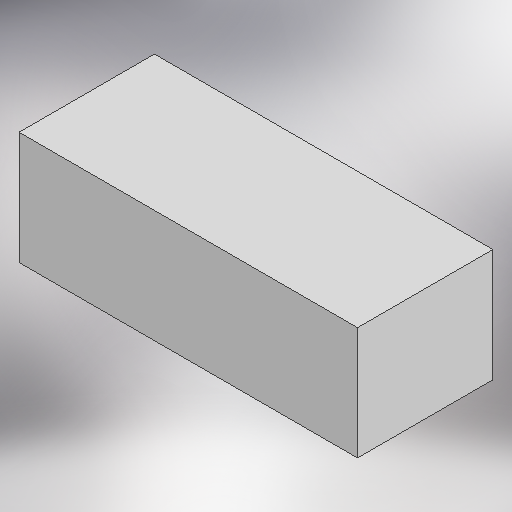
# Autodesk Inventor part: new_linked
Saved by Autodesk Inventor 2026 (Build 300175000, 175)
## iProperties
Created: 2026-10-20
Part Number: new_linked
Material: Generic
Document SubType Name: Modeling
Designer: 2ndlo
Density: 1 g/cm^3
Appearance: Default
Author: 2ndlo
Autodesk Inventor part; units mm, degrees
ref_plane "YZ Plane" through (0, 0, 0) normal (1, 0, 0) x (0, 1, 0)
ref_plane "XZ Plane" through (0, 0, 0) normal (0, 1, 0) x (-1, 0, 0)
ref_plane "XY Plane" through (0, 0, 0) normal (0, 0, 1) x (1, 0, 0)
sketch "Sketch1" plane through (0, 0, 0) normal (0, 0, 1) x (1, 0, 0)
  line L0 (0, 0) -> (20, 0)
  line L1 (20, 0) -> (20, 6.6667)
  line L2 (20, 6.6667) -> (0, 6.6667)
  line L3 (0, 6.6667) -> (0, 0)
  dimension "d2" = 20
  dimension "d3" = 20
  constraints: 8 end point, 2 parallel, 1 horizontal, 1 perpendicular
  measures "d2" distance of L1.end L2.end
  measures "d3" distance of L0.start L0.end
extrude "Extrusion1" add sketch "Sketch1" along normal blind 8
equation "\"d2\" = MyWidth"
equation "\"MyWidth\" = 20"
body "Solid1"
